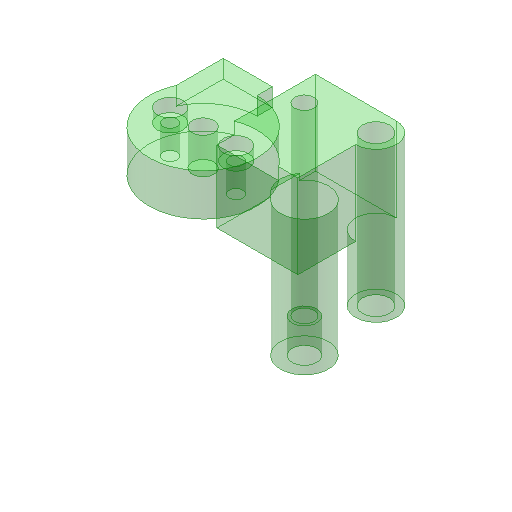
# Autodesk Inventor part: OT2-Pipette V0.6 - yoke eject variant
Saved by Autodesk Inventor 2025.5 (Build 295498000, 498)
## iProperties
Created: 2026-11-20
Part Number: OT2-Pipette V0.6 - yoke eject variant
Material: Generisch
Description: printed yoke, eject variant: 2 M2 pins for the spring pad, rear arm on the 4 mm guide rod, push post with M3 set screw
Document SubType Name: Modeling
Designer: benir
Density: 1 g/cm^3
Appearance: Green
Author: benir
Autodesk Inventor part; units mm, degrees
ref_plane "y=top_y - disc_h" through (0, 99, 0) normal (0, 1, 0) x (-1, 0, 0)
sketch "disc" plane through (0, 99, 0) normal (0, 1, 0) x (-1, 0, 0)
  circle A0 centre (-8.2, -3.46) radius 9
  point P0 (0, 0)
  dimension "d3" = 3.46
  dimension "d4" = 8.2
  dimension "d5" = 18
  constraints: 1 centre point
  measures "d3" vertical distance of point (0, 0) A0.centre
  measures "d4" horizontal distance of point (0, 0) A0.centre
  measures "d5" diameter of A0
extrude "Extrusion2" add sketch "disc" along normal blind 7
ref_plane "y=arm_y0" through (0, 87, 0) normal (0, 1, 0) x (-1, 0, 0)
sketch "arm block" plane through (0, 87, 0) normal (0, 1, 0) x (-1, 0, 0)
  line L0 (-5, -25.4) -> (-18.5, -25.4)
  line L1 (-18.5, -25.4) -> (-18.5, -8.96)
  line L2 (-18.5, -8.96) -> (-5, -8.96)
  line L3 (-5, -8.96) -> (-5, -25.4)
  line L4 (0, -31.588) -> (0, 11.728) projected
  line L5 (4.66, 0) -> (-22.36, 0) projected
  point P0 (0, 0)
  dimension "d9" = 13.5
  dimension "d10" = 16.44
  dimension "d11" = 5
  dimension "d12" = 25.4
  constraints: 8 end point, 2 parallel, 1 horizontal, 1 perpendicular
  measures "d9" distance of L0.start L0.end
  measures "d10" distance of L2.end L0.start
  measures "d11" horizontal distance of point (0, 0) L2.end
  measures "d12" vertical distance of point (0, 0) L0.start
extrude "Extrusion3" add sketch "arm block" along normal blind 14
ref_plane "y=arm_y1 - bush_len" through (0, 76, 0) normal (0, 1, 0) x (-1, 0, 0)
sketch "bushing" plane through (0, 76, 0) normal (0, 1, 0) x (-1, 0, 0)
  circle A0 centre (-18.5, -22) radius 3.4
  point P0 (0, 0)
  dimension "d16" = 22
  dimension "d17" = 18.5
  dimension "d18" = 6.8
  constraints: 1 centre point
  measures "d16" vertical distance of point (0, 0) A0.centre
  measures "d17" horizontal distance of point (0, 0) A0.centre
  measures "d18" diameter of A0
extrude "bushing on the guide rod" add sketch "bushing" along normal blind 25
ref_plane "y=arm_boss_y" through (0, 64.5, 0) normal (0, 1, 0) x (-1, 0, 0)
sketch "push post" plane through (0, 64.5, 0) normal (0, 1, 0) x (-1, 0, 0)
  circle A0 centre (-8.2, -20.36) radius 4
  point P0 (0, 0)
  dimension "d22" = 20.36
  dimension "d23" = 8.2
  dimension "d24" = 8
  constraints: 1 centre point
  measures "d22" vertical distance of point (0, 0) A0.centre
  measures "d23" horizontal distance of point (0, 0) A0.centre
  measures "d24" diameter of A0
extrude "Extrusion5" add sketch "push post" along normal blind 23.5
ref_plane "y=arm_y1 - bush_len - cut_over" through (0, 75, 0) normal (0, 1, 0) x (-1, 0, 0)
sketch "bushing bore" plane through (0, 75, 0) normal (0, 1, 0) x (-1, 0, 0)
  circle A0 centre (-18.5, -22) radius 2.25
  point P0 (0, 0)
  dimension "d28" = 22
  dimension "d29" = 18.5
  dimension "d30" = 4.5
  constraints: 1 centre point
  measures "d28" vertical distance of point (0, 0) A0.centre
  measures "d29" horizontal distance of point (0, 0) A0.centre
  measures "d30" diameter of A0
extrude "Extrusion6" cut sketch "bushing bore" along normal blind 27
ref_plane "y=arm_boss_y - cut_over" through (0, 63.5, 0) normal (0, 1, 0) x (-1, 0, 0)
sketch "set screw insert" plane through (0, 63.5, 0) normal (0, 1, 0) x (-1, 0, 0)
  circle A0 centre (-8.2, -20.36) radius 2.05
  point P0 (0, 0)
  dimension "d34" = 20.36
  dimension "d35" = 8.2
  dimension "d36" = 4.1
  constraints: 1 centre point
  measures "d34" vertical distance of point (0, 0) A0.centre
  measures "d35" horizontal distance of point (0, 0) A0.centre
  measures "d36" diameter of A0
extrude "M3 insert hole (set screw)" cut sketch "set screw insert" along normal blind 6.7
sketch "hex key bore" plane through (0, 64.5, 0) normal (0, 1, 0) x (-1, 0, 0)
  circle A0 centre (-8.2, -20.36) radius 1.6
  point P0 (0, 0)
  dimension "d39" = 20.36
  dimension "d40" = 8.2
  dimension "d41" = 3.2
  constraints: 1 centre point
  measures "d39" vertical distance of point (0, 0) A0.centre
  measures "d40" horizontal distance of point (0, 0) A0.centre
  measures "d41" diameter of A0
extrude "Extrusion8" cut sketch "hex key bore" along normal blind 37.5
ref_plane "y=top_y - tab_h" through (0, 103, 0) normal (0, 1, 0) x (-1, 0, 0)
sketch "switch tab" plane through (0, 103, 0) normal (0, 1, 0) x (-1, 0, 0)
  line L0 (0, -15) -> (-8.2, -15)
  line L1 (-8.2, -15) -> (-8.2, -3.46)
  line L2 (-8.2, -3.46) -> (0, -3.46)
  line L3 (0, -3.46) -> (0, -15)
  line L4 (0, -31.588) -> (0, 11.728) projected
  line L5 (5.34, 0) -> (-26.44, 0) projected
  point P0 (0, 0)
  dimension "d45" = 8.2
  dimension "d46" = 11.54
  dimension "d47" = 15
  constraints: 8 end point, 2 parallel, 1 collinear, 1 horizontal, 1 perpendicular
  measures "d45" distance of L0.start L0.end
  measures "d46" distance of L2.end L0.start
  measures "d47" distance of point (0, 0) L0.start
extrude "Extrusion9" add sketch "switch tab" along normal blind 3
ref_plane "y=top_y - insert_m25_depth" through (0, 100, 0) normal (0, 1, 0) x (-1, 0, 0)
sketch "M2.5 insert hole" plane through (0, 100, 0) normal (0, 1, 0) x (-1, 0, 0)
  circle A0 centre (-8.2, -3.46) radius 1.8
  point P0 (0, 0)
  dimension "d51" = 3.46
  dimension "d52" = 8.2
  dimension "d53" = 3.6
  constraints: 1 centre point
  measures "d51" vertical distance of point (0, 0) A0.centre
  measures "d52" horizontal distance of point (0, 0) A0.centre
  measures "d53" diameter of A0
extrude "Extrusion10" cut sketch "M2.5 insert hole" along normal blind 7
ref_plane "y=top_y - disc_h - cut_over" through (0, 98, 0) normal (0, 1, 0) x (-1, 0, 0)
sketch "pin holes" plane through (0, 98, 0) normal (0, 1, 0) x (-1, 0, 0)
  circle A0 centre (-2.7, -3.46) radius 1.15
  circle A1 centre (-13.7, -3.46) radius 1.15
  point P0 (0, 0)
  dimension "d57" = 3.46
  dimension "d58" = 2.7
  dimension "d59" = 2.3
  dimension "d60" = 3.46
  dimension "d61" = 13.7
  dimension "d62" = 2.3
  constraints: 2 centre point
  measures "d57" vertical distance of point (0, 0) A0.centre
  measures "d58" horizontal distance of point (0, 0) A0.centre
  measures "d59" diameter of A0
  measures "d60" vertical distance of point (0, 0) A1.centre
  measures "d61" horizontal distance of point (0, 0) A1.centre
  measures "d62" diameter of A1
extrude "M2 pin holes" cut sketch "pin holes" along normal blind 9
ref_plane "y=top_y - pin_cb_h" through (0, 103.8, 0) normal (0, 1, 0) x (-1, 0, 0)
sketch "pin head counterbores" plane through (0, 103.8, 0) normal (0, 1, 0) x (-1, 0, 0)
  circle A0 centre (-2.7, -3.46) radius 2.1
  circle A1 centre (-13.7, -3.46) radius 2.1
  point P0 (0, 0)
  dimension "d66" = 3.46
  dimension "d67" = 2.7
  dimension "d68" = 4.2
  dimension "d69" = 3.46
  dimension "d70" = 13.7
  dimension "d71" = 4.2
  constraints: 2 centre point
  measures "d66" vertical distance of point (0, 0) A0.centre
  measures "d67" horizontal distance of point (0, 0) A0.centre
  measures "d68" diameter of A0
  measures "d69" vertical distance of point (0, 0) A1.centre
  measures "d70" horizontal distance of point (0, 0) A1.centre
  measures "d71" diameter of A1
extrude "Extrusion12" cut sketch "pin head counterbores" along normal blind 3.2
equation "\"d3\" = -pip_z"
equation "\"d4\" = pip_x"
equation "\"d5\" = yoke_d"
equation "\"d6\" = disc_h"
equation "\"d9\" = rod_x - arm_x0"
equation "\"d10\" = -arm_d0 + pip_z + 0.5 * bush_od - rod_z"
equation "\"d11\" = arm_x0"
equation "\"d12\" = 0.5 * bush_od - rod_z"
equation "\"d13\" = arm_h"
equation "\"d16\" = -rod_z"
equation "\"d17\" = rod_x"
equation "\"d18\" = bush_od"
equation "\"d19\" = bush_len"
equation "\"d22\" = -post_z"
equation "\"d23\" = pip_x"
equation "\"d24\" = post_d"
equation "\"d25\" = -arm_boss_y + arm_y0 + cut_over"
equation "\"d28\" = -rod_z"
equation "\"d29\" = rod_x"
equation "\"d30\" = rod_d + 2 * bush_clr"
equation "\"d31\" = bush_len + 2 * cut_over"
equation "\"d34\" = -post_z"
equation "\"d35\" = pip_x"
equation "\"d36\" = post_ins_d"
equation "\"d37\" = post_ins_h + cut_over"
equation "\"d39\" = -post_z"
equation "\"d40\" = pip_x"
equation "\"d41\" = post_bore_d"
equation "\"d42\" = -arm_boss_y + arm_y1 + cut_over"
equation "\"d45\" = pip_x - tab_x0"
equation "\"d46\" = pip_z - tab_z_in - sw_z0"
equation "\"d47\" = -tab_z_in - sw_z0"
equation "\"d48\" = tab_h"
equation "\"d51\" = -pip_z"
equation "\"d52\" = pip_x"
equation "\"d53\" = insert_m25"
equation "\"d54\" = insert_m25_depth + cut_over"
equation "\"d57\" = -pip_z"
equation "\"d58\" = pip_x - pin_r"
equation "\"d59\" = pin_clear_d"
equation "\"d60\" = -pip_z"
equation "\"d61\" = pip_x + pin_r"
equation "\"d62\" = pin_clear_d"
equation "\"d63\" = disc_h + 2 * cut_over"
equation "\"d66\" = -pip_z"
equation "\"d67\" = pip_x - pin_r"
equation "\"d68\" = pin_cb_d"
equation "\"d69\" = -pip_z"
equation "\"d70\" = pip_x + pin_r"
equation "\"d71\" = pin_cb_d"
equation "\"d72\" = pin_cb_h + cut_over"
equation "\"yoke_d\" = 18"
equation "\"disc_h\" = 7"
equation "\"rod_x\" = 18.5"
equation "\"arm_x0\" = 5"
equation "\"arm_d0\" = 5.5"
equation "\"pip_z\" = -3.46"
equation "\"bush_od\" = 6.8"
equation "\"rod_z\" = -22"
equation "\"arm_h\" = 14"
equation "\"bush_len\" = 25"
equation "\"post_d\" = 8"
equation "\"arm_boss_y\" = 64.5"
equation "\"arm_y0\" = 87"
equation "\"cut_over\" = 1"
equation "\"rod_d\" = 4"
equation "\"bush_clr\" = 0.25"
equation "\"post_ins_d\" = 4.1"
equation "\"post_ins_h\" = 5.7"
equation "\"post_bore_d\" = 3.2"
equation "\"arm_y1\" = 101"
equation "\"pip_x\" = 8.2"
equation "\"tab_x0\" = 0"
equation "\"tab_z_in\" = 1"
equation "\"sw_z0\" = -16"
equation "\"tab_h\" = 3"
equation "\"insert_m25\" = 3.6"
equation "\"insert_m25_depth\" = 6"
equation "\"pin_clear_d\" = 2.3"
equation "\"pin_cb_d\" = 4.2"
equation "\"pin_cb_h\" = 2.2"
equation "\"post_z\" = -20.36"
equation "\"pin_r\" = 5.5"
body "Solid2"
